Autodesk Fusion 360 part; units mm, degrees
(part 4 of 7)
equation "d92 = abs(( 1 ) * ( ( ( 1 ) * jointNodeQ * sqrt(2) - bodyWidth / 2 * cos(0 deg) + ( ( 1 ) * nodeHalfWidth ) * sin(0 deg) ) + ( 0.833333333333333 ) * ( ( 1 ) * endNodeX - ( ( 1 ) * jointNodeQ * sqrt(2) - bodyWidth / 2 * cos(0 deg) + ( ( 1 ) * nodeHalfWidth ) * sin(0 deg) ) ) ) + ( 0 ) * ( ( 1 ) * nodeHalfWidth ))"
equation "d93 = abs(( 0 ) * ( ( ( 1 ) * jointNodeQ * sqrt(2) - bodyWidth / 2 * cos(0 deg) + ( ( 1 ) * nodeHalfWidth ) * sin(0 deg) ) + ( 0.833333333333333 ) * ( ( 1 ) * endNodeX - ( ( 1 ) * jointNodeQ * sqrt(2) - bodyWidth / 2 * cos(0 deg) + ( ( 1 ) * nodeHalfWidth ) * sin(0 deg) ) ) ) + ( -1 ) * ( ( 1 ) * nodeHalfWidth ))"
equation "d94 = abs(( 1 ) * ( ( ( 1 ) * jointNodeQ * sqrt(2) - bodyWidth / 2 * cos(0 deg) + ( ( -1 ) * nodeHalfWidth ) * sin(0 deg) ) + ( 1 ) * ( ( 1 ) * endNodeX - ( ( 1 ) * jointNodeQ * sqrt(2) - bodyWidth / 2 * cos(0 deg) + ( ( -1 ) * nodeHalfWidth ) * sin(0 deg) ) ) ) + ( 0 ) * ( ( -1 ) * nodeHalfWidth ))"
equation "d95 = abs(( 0 ) * ( ( ( 1 ) * jointNodeQ * sqrt(2) - bodyWidth / 2 * cos(0 deg) + ( ( -1 ) * nodeHalfWidth ) * sin(0 deg) ) + ( 1 ) * ( ( 1 ) * endNodeX - ( ( 1 ) * jointNodeQ * sqrt(2) - bodyWidth / 2 * cos(0 deg) + ( ( -1 ) * nodeHalfWidth ) * sin(0 deg) ) ) ) + ( -1 ) * ( ( -1 ) * nodeHalfWidth ))"
equation "d96 = -memberWidth / 2"
equation "d97 = -( wall + 0.2 mm )"
equation "d99 = abs(( 1 ) * ( ( ( 1 ) * jointNodeQ * sqrt(2) - bodyWidth / 2 * cos(0 deg) + ( ( 1 ) * nodeHalfWidth ) * sin(0 deg) ) + ( 0.833333333333333 ) * ( ( 1 ) * endNodeX - ( ( 1 ) * jointNodeQ * sqrt(2) - bodyWidth / 2 * cos(0 deg) + ( ( 1 ) * nodeHalfWidth ) * sin(0 deg) ) ) ) + ( 0 ) * ( ( 1 ) * nodeHalfWidth ))"
equation "d100 = abs(( 0 ) * ( ( ( 1 ) * jointNodeQ * sqrt(2) - bodyWidth / 2 * cos(0 deg) + ( ( 1 ) * nodeHalfWidth ) * sin(0 deg) ) + ( 0.833333333333333 ) * ( ( 1 ) * endNodeX - ( ( 1 ) * jointNodeQ * sqrt(2) - bodyWidth / 2 * cos(0 deg) + ( ( 1 ) * nodeHalfWidth ) * sin(0 deg) ) ) ) + ( -1 ) * ( ( 1 ) * nodeHalfWidth ))"
equation "d101 = abs(( 1 ) * ( ( ( 1 ) * jointNodeQ * sqrt(2) - bodyWidth / 2 * cos(0 deg) + ( ( -1 ) * nodeHalfWidth ) * sin(0 deg) ) + ( 1 ) * ( ( 1 ) * endNodeX - ( ( 1 ) * jointNodeQ * sqrt(2) - bodyWidth / 2 * cos(0 deg) + ( ( -1 ) * nodeHalfWidth ) * sin(0 deg) ) ) ) + ( 0 ) * ( ( -1 ) * nodeHalfWidth ))"
equation "d102 = abs(( 0 ) * ( ( ( 1 ) * jointNodeQ * sqrt(2) - bodyWidth / 2 * cos(0 deg) + ( ( -1 ) * nodeHalfWidth ) * sin(0 deg) ) + ( 1 ) * ( ( 1 ) * endNodeX - ( ( 1 ) * jointNodeQ * sqrt(2) - bodyWidth / 2 * cos(0 deg) + ( ( -1 ) * nodeHalfWidth ) * sin(0 deg) ) ) ) + ( -1 ) * ( ( -1 ) * nodeHalfWidth ))"
equation "d103 = abs(( 1 ) * ( ( ( 1 ) * jointNodeQ * sqrt(2) - bodyWidth / 2 * cos(0 deg) + ( ( 1 ) * nodeHalfWidth ) * sin(0 deg) ) + ( 1 ) * ( ( 1 ) * endNodeX - ( ( 1 ) * jointNodeQ * sqrt(2) - bodyWidth / 2 * cos(0 deg) + ( ( 1 ) * nodeHalfWidth ) * sin(0 deg) ) ) ) + ( 0 ) * ( ( 1 ) * nodeHalfWidth ))"
equation "d104 = abs(( 0 ) * ( ( ( 1 ) * jointNodeQ * sqrt(2) - bodyWidth / 2 * cos(0 deg) + ( ( 1 ) * nodeHalfWidth ) * sin(0 deg) ) + ( 1 ) * ( ( 1 ) * endNodeX - ( ( 1 ) * jointNodeQ * sqrt(2) - bodyWidth / 2 * cos(0 deg) + ( ( 1 ) * nodeHalfWidth ) * sin(0 deg) ) ) ) + ( -1 ) * ( ( 1 ) * nodeHalfWidth ))"
equation "d105 = memberWidth / 2"
equation "d106 = -( wall + 0.2 mm )"
equation "d109 = apertureRadius"
equation "d112 = bodyWidth / 2"
equation "d114 = abs(( 1 ) * ( ( ( 1 ) * jointNodeQ * sqrt(2) - bodyWidth / 2 * cos(45 deg) + ( ( -1 ) * nodeHalfWidth ) * sin(45 deg) ) + ( 0 ) * ( ( 1 ) * endNodeX - ( ( 1 ) * jointNodeQ * sqrt(2) - bodyWidth / 2 * cos(45 deg) + ( ( -1 ) * nodeHalfWidth ) * sin(45 deg) ) ) ) + ( 0 ) * ( ( -1 ) * nodeHalfWidth ))"
equation "d115 = abs(( 0 ) * ( ( ( 1 ) * jointNodeQ * sqrt(2) - bodyWidth / 2 * cos(45 deg) + ( ( -1 ) * nodeHalfWidth ) * sin(45 deg) ) + ( 0 ) * ( ( 1 ) * endNodeX - ( ( 1 ) * jointNodeQ * sqrt(2) - bodyWidth / 2 * cos(45 deg) + ( ( -1 ) * nodeHalfWidth ) * sin(45 deg) ) ) ) + ( -1 ) * ( ( -1 ) * nodeHalfWidth ))"
equation "d116 = abs(( 1 ) * ( ( ( 1 ) * jointNodeQ * sqrt(2) - bodyWidth / 2 * cos(45 deg) + ( ( 1 ) * nodeHalfWidth ) * sin(45 deg) ) + ( 0 ) * ( ( 1 ) * endNodeX - ( ( 1 ) * jointNodeQ * sqrt(2) - bodyWidth / 2 * cos(45 deg) + ( ( 1 ) * nodeHalfWidth ) * sin(45 deg) ) ) ) + ( 0 ) * ( ( 1 ) * nodeHalfWidth ))"
equation "d117 = abs(( 0 ) * ( ( ( 1 ) * jointNodeQ * sqrt(2) - bodyWidth / 2 * cos(45 deg) + ( ( 1 ) * nodeHalfWidth ) * sin(45 deg) ) + ( 0 ) * ( ( 1 ) * endNodeX - ( ( 1 ) * jointNodeQ * sqrt(2) - bodyWidth / 2 * cos(45 deg) + ( ( 1 ) * nodeHalfWidth ) * sin(45 deg) ) ) ) + ( -1 ) * ( ( 1 ) * nodeHalfWidth ))"
equation "d118 = abs(( 1 ) * ( ( ( 1 ) * jointNodeQ * sqrt(2) - bodyWidth / 2 * cos(45 deg) + ( ( -1 ) * nodeHalfWidth ) * sin(45 deg) ) + ( 0.333333333333333 ) * ( ( 1 ) * endNodeX - ( ( 1 ) * jointNodeQ * sqrt(2) - bodyWidth / 2 * cos(45 deg) + ( ( -1 ) * nodeHalfWidth ) * sin(45 deg) ) ) ) + ( 0 ) * ( ( -1 ) * nodeHalfWidth ))"
equation "d119 = abs(( 0 ) * ( ( ( 1 ) * jointNodeQ * sqrt(2) - bodyWidth / 2 * cos(45 deg) + ( ( -1 ) * nodeHalfWidth ) * sin(45 deg) ) + ( 0.333333333333333 ) * ( ( 1 ) * endNodeX - ( ( 1 ) * jointNodeQ * sqrt(2) - bodyWidth / 2 * cos(45 deg) + ( ( -1 ) * nodeHalfWidth ) * sin(45 deg) ) ) ) + ( -1 ) * ( ( -1 ) * nodeHalfWidth ))"
equation "d120 = -memberWidth / 2"
equation "d121 = -( wall + 0.2 mm )"
equation "d123 = abs(( 1 ) * ( ( ( 1 ) * jointNodeQ * sqrt(2) - bodyWidth / 2 * cos(45 deg) + ( ( 1 ) * nodeHalfWidth ) * sin(45 deg) ) + ( 0 ) * ( ( 1 ) * endNodeX - ( ( 1 ) * jointNodeQ * sqrt(2) - bodyWidth / 2 * cos(45 deg) + ( ( 1 ) * nodeHalfWidth ) * sin(45 deg) ) ) ) + ( 0 ) * ( ( 1 ) * nodeHalfWidth ))"
equation "d124 = abs(( 0 ) * ( ( ( 1 ) * jointNodeQ * sqrt(2) - bodyWidth / 2 * cos(45 deg) + ( ( 1 ) * nodeHalfWidth ) * sin(45 deg) ) + ( 0 ) * ( ( 1 ) * endNodeX - ( ( 1 ) * jointNodeQ * sqrt(2) - bodyWidth / 2 * cos(45 deg) + ( ( 1 ) * nodeHalfWidth ) * sin(45 deg) ) ) ) + ( -1 ) * ( ( 1 ) * nodeHalfWidth ))"
equation "d125 = abs(( 1 ) * ( ( ( 1 ) * jointNodeQ * sqrt(2) - bodyWidth / 2 * cos(45 deg) + ( ( -1 ) * nodeHalfWidth ) * sin(45 deg) ) + ( 0.333333333333333 ) * ( ( 1 ) * endNodeX - ( ( 1 ) * jointNodeQ * sqrt(2) - bodyWidth / 2 * cos(45 deg) + ( ( -1 ) * nodeHalfWidth ) * sin(45 deg) ) ) ) + ( 0 ) * ( ( -1 ) * nodeHalfWidth ))"
equation "d126 = abs(( 0 ) * ( ( ( 1 ) * jointNodeQ * sqrt(2) - bodyWidth / 2 * cos(45 deg) + ( ( -1 ) * nodeHalfWidth ) * sin(45 deg) ) + ( 0.333333333333333 ) * ( ( 1 ) * endNodeX - ( ( 1 ) * jointNodeQ * sqrt(2) - bodyWidth / 2 * cos(45 deg) + ( ( -1 ) * nodeHalfWidth ) * sin(45 deg) ) ) ) + ( -1 ) * ( ( -1 ) * nodeHalfWidth ))"
equation "d127 = abs(( 1 ) * ( ( ( 1 ) * jointNodeQ * sqrt(2) - bodyWidth / 2 * cos(45 deg) + ( ( 1 ) * nodeHalfWidth ) * sin(45 deg) ) + ( 0.666666666666667 ) * ( ( 1 ) * endNodeX - ( ( 1 ) * jointNodeQ * sqrt(2) - bodyWidth / 2 * cos(45 deg) + ( ( 1 ) * nodeHalfWidth ) * sin(45 deg) ) ) ) + ( 0 ) * ( ( 1 ) * nodeHalfWidth ))"
equation "d128 = abs(( 0 ) * ( ( ( 1 ) * jointNodeQ * sqrt(2) - bodyWidth / 2 * cos(45 deg) + ( ( 1 ) * nodeHalfWidth ) * sin(45 deg) ) + ( 0.666666666666667 ) * ( ( 1 ) * endNodeX - ( ( 1 ) * jointNodeQ * sqrt(2) - bodyWidth / 2 * cos(45 deg) + ( ( 1 ) * nodeHalfWidth ) * sin(45 deg) ) ) ) + ( -1 ) * ( ( 1 ) * nodeHalfWidth ))"
equation "d129 = memberWidth / 2"
equation "d130 = -( wall + 0.2 mm )"
equation "d132 = abs(( 1 ) * ( ( ( 1 ) * jointNodeQ * sqrt(2) - bodyWidth / 2 * cos(45 deg) + ( ( -1 ) * nodeHalfWidth ) * sin(45 deg) ) + ( 0.333333333333333 ) * ( ( 1 ) * endNodeX - ( ( 1 ) * jointNodeQ * sqrt(2) - bodyWidth / 2 * cos(45 deg) + ( ( -1 ) * nodeHalfWidth ) * sin(45 deg) ) ) ) + ( 0 ) * ( ( -1 ) * nodeHalfWidth ))"
equation "d133 = abs(( 0 ) * ( ( ( 1 ) * jointNodeQ * sqrt(2) - bodyWidth / 2 * cos(45 deg) + ( ( -1 ) * nodeHalfWidth ) * sin(45 deg) ) + ( 0.333333333333333 ) * ( ( 1 ) * endNodeX - ( ( 1 ) * jointNodeQ * sqrt(2) - bodyWidth / 2 * cos(45 deg) + ( ( -1 ) * nodeHalfWidth ) * sin(45 deg) ) ) ) + ( -1 ) * ( ( -1 ) * nodeHalfWidth ))"
equation "d134 = abs(( 1 ) * ( ( ( 1 ) * jointNodeQ * sqrt(2) - bodyWidth / 2 * cos(45 deg) + ( ( 1 ) * nodeHalfWidth ) * sin(45 deg) ) + ( 0.666666666666667 ) * ( ( 1 ) * endNodeX - ( ( 1 ) * jointNodeQ * sqrt(2) - bodyWidth / 2 * cos(45 deg) + ( ( 1 ) * nodeHalfWidth ) * sin(45 deg) ) ) ) + ( 0 ) * ( ( 1 ) * nodeHalfWidth ))"
equation "d135 = abs(( 0 ) * ( ( ( 1 ) * jointNodeQ * sqrt(2) - bodyWidth / 2 * cos(45 deg) + ( ( 1 ) * nodeHalfWidth ) * sin(45 deg) ) + ( 0.666666666666667 ) * ( ( 1 ) * endNodeX - ( ( 1 ) * jointNodeQ * sqrt(2) - bodyWidth / 2 * cos(45 deg) + ( ( 1 ) * nodeHalfWidth ) * sin(45 deg) ) ) ) + ( -1 ) * ( ( 1 ) * nodeHalfWidth ))"
equation "d136 = abs(( 1 ) * ( ( ( 1 ) * jointNodeQ * sqrt(2) - bodyWidth / 2 * cos(45 deg) + ( ( -1 ) * nodeHalfWidth ) * sin(45 deg) ) + ( 1 ) * ( ( 1 ) * endNodeX - ( ( 1 ) * jointNodeQ * sqrt(2) - bodyWidth / 2 * cos(45 deg) + ( ( -1 ) * nodeHalfWidth ) * sin(45 deg) ) ) ) + ( 0 ) * ( ( -1 ) * nodeHalfWidth ))"
equation "d137 = abs(( 0 ) * ( ( ( 1 ) * jointNodeQ * sqrt(2) - bodyWidth / 2 * cos(45 deg) + ( ( -1 ) * nodeHalfWidth ) * sin(45 deg) ) + ( 1 ) * ( ( 1 ) * endNodeX - ( ( 1 ) * jointNodeQ * sqrt(2) - bodyWidth / 2 * cos(45 deg) + ( ( -1 ) * nodeHalfWidth ) * sin(45 deg) ) ) ) + ( -1 ) * ( ( -1 ) * nodeHalfWidth ))"
equation "d138 = -memberWidth / 2"
equation "d139 = -( wall + 0.2 mm )"
equation "d141 = abs(( 1 ) * ( ( ( 1 ) * jointNodeQ * sqrt(2) - bodyWidth / 2 * cos(45 deg) + ( ( 1 ) * nodeHalfWidth ) * sin(45 deg) ) + ( 0.666666666666667 ) * ( ( 1 ) * endNodeX - ( ( 1 ) * jointNodeQ * sqrt(2) - bodyWidth / 2 * cos(45 deg) + ( ( 1 ) * nodeHalfWidth ) * sin(45 deg) ) ) ) + ( 0 ) * ( ( 1 ) * nodeHalfWidth ))"
equation "d142 = abs(( 0 ) * ( ( ( 1 ) * jointNodeQ * sqrt(2) - bodyWidth / 2 * cos(45 deg) + ( ( 1 ) * nodeHalfWidth ) * sin(45 deg) ) + ( 0.666666666666667 ) * ( ( 1 ) * endNodeX - ( ( 1 ) * jointNodeQ * sqrt(2) - bodyWidth / 2 * cos(45 deg) + ( ( 1 ) * nodeHalfWidth ) * sin(45 deg) ) ) ) + ( -1 ) * ( ( 1 ) * nodeHalfWidth ))"
equation "d143 = abs(( 1 ) * ( ( ( 1 ) * jointNodeQ * sqrt(2) - bodyWidth / 2 * cos(45 deg) + ( ( -1 ) * nodeHalfWidth ) * sin(45 deg) ) + ( 1 ) * ( ( 1 ) * endNodeX - ( ( 1 ) * jointNodeQ * sqrt(2) - bodyWidth / 2 * cos(45 deg) + ( ( -1 ) * nodeHalfWidth ) * sin(45 deg) ) ) ) + ( 0 ) * ( ( -1 ) * nodeHalfWidth ))"
equation "d144 = abs(( 0 ) * ( ( ( 1 ) * jointNodeQ * sqrt(2) - bodyWidth / 2 * cos(45 deg) + ( ( -1 ) * nodeHalfWidth ) * sin(45 deg) ) + ( 1 ) * ( ( 1 ) * endNodeX - ( ( 1 ) * jointNodeQ * sqrt(2) - bodyWidth / 2 * cos(45 deg) + ( ( -1 ) * nodeHalfWidth ) * sin(45 deg) ) ) ) + ( -1 ) * ( ( -1 ) * nodeHalfWidth ))"
equation "d145 = abs(( 1 ) * ( ( ( 1 ) * jointNodeQ * sqrt(2) - bodyWidth / 2 * cos(45 deg) + ( ( 1 ) * nodeHalfWidth ) * sin(45 deg) ) + ( 1 ) * ( ( 1 ) * endNodeX - ( ( 1 ) * jointNodeQ * sqrt(2) - bodyWidth / 2 * cos(45 deg) + ( ( 1 ) * nodeHalfWidth ) * sin(45 deg) ) ) ) + ( 0 ) * ( ( 1 ) * nodeHalfWidth ))"
equation "d146 = abs(( 0 ) * ( ( ( 1 ) * jointNodeQ * sqrt(2) - bodyWidth / 2 * cos(45 deg) + ( ( 1 ) * nodeHalfWidth ) * sin(45 deg) ) + ( 1 ) * ( ( 1 ) * endNodeX - ( ( 1 ) * jointNodeQ * sqrt(2) - bodyWidth / 2 * cos(45 deg) + ( ( 1 ) * nodeHalfWidth ) * sin(45 deg) ) ) ) + ( -1 ) * ( ( 1 ) * nodeHalfWidth ))"
equation "d147 = memberWidth / 2"
equation "d148 = -( wall + 0.2 mm )"
equation "d151 = apertureRadius"
equation "d154 = bodyWidth / 2"
equation "d156 = abs(( 1 ) * ( ( ( 1 ) * jointNodeQ * sqrt(2) - bodyWidth / 2 * cos(90 deg) + ( ( -1 ) * nodeHalfWidth ) * sin(90 deg) ) + ( 0 ) * ( ( 1 ) * endNodeX - ( ( 1 ) * jointNodeQ * sqrt(2) - bodyWidth / 2 * cos(90 deg) + ( ( -1 ) * nodeHalfWidth ) * sin(90 deg) ) ) ) + ( 0 ) * ( ( -1 ) * nodeHalfWidth ))"
equation "d157 = abs(( 0 ) * ( ( ( 1 ) * jointNodeQ * sqrt(2) - bodyWidth / 2 * cos(90 deg) + ( ( -1 ) * nodeHalfWidth ) * sin(90 deg) ) + ( 0 ) * ( ( 1 ) * endNodeX - ( ( 1 ) * jointNodeQ * sqrt(2) - bodyWidth / 2 * cos(90 deg) + ( ( -1 ) * nodeHalfWidth ) * sin(90 deg) ) ) ) + ( -1 ) * ( ( -1 ) * nodeHalfWidth ))"
equation "d158 = abs(( 1 ) * ( ( ( 1 ) * jointNodeQ * sqrt(2) - bodyWidth / 2 * cos(90 deg) + ( ( 1 ) * nodeHalfWidth ) * sin(90 deg) ) + ( 0 ) * ( ( 1 ) * endNodeX - ( ( 1 ) * jointNodeQ * sqrt(2) - bodyWidth / 2 * cos(90 deg) + ( ( 1 ) * nodeHalfWidth ) * sin(90 deg) ) ) ) + ( 0 ) * ( ( 1 ) * nodeHalfWidth ))"
equation "d159 = abs(( 0 ) * ( ( ( 1 ) * jointNodeQ * sqrt(2) - bodyWidth / 2 * cos(90 deg) + ( ( 1 ) * nodeHalfWidth ) * sin(90 deg) ) + ( 0 ) * ( ( 1 ) * endNodeX - ( ( 1 ) * jointNodeQ * sqrt(2) - bodyWidth / 2 * cos(90 deg) + ( ( 1 ) * nodeHalfWidth ) * sin(90 deg) ) ) ) + ( -1 ) * ( ( 1 ) * nodeHalfWidth ))"
equation "d160 = abs(( 1 ) * ( ( ( 1 ) * jointNodeQ * sqrt(2) - bodyWidth / 2 * cos(90 deg) + ( ( -1 ) * nodeHalfWidth ) * sin(90 deg) ) + ( 0.5 ) * ( ( 1 ) * endNodeX - ( ( 1 ) * jointNodeQ * sqrt(2) - bodyWidth / 2 * cos(90 deg) + ( ( -1 ) * nodeHalfWidth ) * sin(90 deg) ) ) ) + ( 0 ) * ( ( -1 ) * nodeHalfWidth ))"
equation "d161 = abs(( 0 ) * ( ( ( 1 ) * jointNodeQ * sqrt(2) - bodyWidth / 2 * cos(90 deg) + ( ( -1 ) * nodeHalfWidth ) * sin(90 deg) ) + ( 0.5 ) * ( ( 1 ) * endNodeX - ( ( 1 ) * jointNodeQ * sqrt(2) - bodyWidth / 2 * cos(90 deg) + ( ( -1 ) * nodeHalfWidth ) * sin(90 deg) ) ) ) + ( -1 ) * ( ( -1 ) * nodeHalfWidth ))"
equation "d162 = -memberWidth / 2"
equation "d163 = -( wall + 0.2 mm )"
equation "d165 = abs(( 1 ) * ( ( ( 1 ) * jointNodeQ * sqrt(2) - bodyWidth / 2 * cos(90 deg) + ( ( 1 ) * nodeHalfWidth ) * sin(90 deg) ) + ( 0 ) * ( ( 1 ) * endNodeX - ( ( 1 ) * jointNodeQ * sqrt(2) - bodyWidth / 2 * cos(90 deg) + ( ( 1 ) * nodeHalfWidth ) * sin(90 deg) ) ) ) + ( 0 ) * ( ( 1 ) * nodeHalfWidth ))"
equation "d166 = abs(( 0 ) * ( ( ( 1 ) * jointNodeQ * sqrt(2) - bodyWidth / 2 * cos(90 deg) + ( ( 1 ) * nodeHalfWidth ) * sin(90 deg) ) + ( 0 ) * ( ( 1 ) * endNodeX - ( ( 1 ) * jointNodeQ * sqrt(2) - bodyWidth / 2 * cos(90 deg) + ( ( 1 ) * nodeHalfWidth ) * sin(90 deg) ) ) ) + ( -1 ) * ( ( 1 ) * nodeHalfWidth ))"
equation "d167 = abs(( 1 ) * ( ( ( 1 ) * jointNodeQ * sqrt(2) - bodyWidth / 2 * cos(90 deg) + ( ( -1 ) * nodeHalfWidth ) * sin(90 deg) ) + ( 0.5 ) * ( ( 1 ) * endNodeX - ( ( 1 ) * jointNodeQ * sqrt(2) - bodyWidth / 2 * cos(90 deg) + ( ( -1 ) * nodeHalfWidth ) * sin(90 deg) ) ) ) + ( 0 ) * ( ( -1 ) * nodeHalfWidth ))"
equation "d168 = abs(( 0 ) * ( ( ( 1 ) * jointNodeQ * sqrt(2) - bodyWidth / 2 * cos(90 deg) + ( ( -1 ) * nodeHalfWidth ) * sin(90 deg) ) + ( 0.5 ) * ( ( 1 ) * endNodeX - ( ( 1 ) * jointNodeQ * sqrt(2) - bodyWidth / 2 * cos(90 deg) + ( ( -1 ) * nodeHalfWidth ) * sin(90 deg) ) ) ) + ( -1 ) * ( ( -1 ) * nodeHalfWidth ))"
equation "d169 = abs(( 1 ) * ( ( ( 1 ) * jointNodeQ * sqrt(2) - bodyWidth / 2 * cos(90 deg) + ( ( 1 ) * nodeHalfWidth ) * sin(90 deg) ) + ( 1 ) * ( ( 1 ) * endNodeX - ( ( 1 ) * jointNodeQ * sqrt(2) - bodyWidth / 2 * cos(90 deg) + ( ( 1 ) * nodeHalfWidth ) * sin(90 deg) ) ) ) + ( 0 ) * ( ( 1 ) * nodeHalfWidth ))"
equation "d170 = abs(( 0 ) * ( ( ( 1 ) * jointNodeQ * sqrt(2) - bodyWidth / 2 * cos(90 deg) + ( ( 1 ) * nodeHalfWidth ) * sin(90 deg) ) + ( 1 ) * ( ( 1 ) * endNodeX - ( ( 1 ) * jointNodeQ * sqrt(2) - bodyWidth / 2 * cos(90 deg) + ( ( 1 ) * nodeHalfWidth ) * sin(90 deg) ) ) ) + ( -1 ) * ( ( 1 ) * nodeHalfWidth ))"
equation "d171 = memberWidth / 2"
equation "d172 = -( wall + 0.2 mm )"
equation "d174 = abs(( 1 ) * ( ( ( 1 ) * jointNodeQ * sqrt(2) - bodyWidth / 2 * cos(90 deg) + ( ( -1 ) * nodeHalfWidth ) * sin(90 deg) ) + ( 0.5 ) * ( ( 1 ) * endNodeX - ( ( 1 ) * jointNodeQ * sqrt(2) - bodyWidth / 2 * cos(90 deg) + ( ( -1 ) * nodeHalfWidth ) * sin(90 deg) ) ) ) + ( 0 ) * ( ( -1 ) * nodeHalfWidth ))"
equation "d175 = abs(( 0 ) * ( ( ( 1 ) * jointNodeQ * sqrt(2) - bodyWidth / 2 * cos(90 deg) + ( ( -1 ) * nodeHalfWidth ) * sin(90 deg) ) + ( 0.5 ) * ( ( 1 ) * endNodeX - ( ( 1 ) * jointNodeQ * sqrt(2) - bodyWidth / 2 * cos(90 deg) + ( ( -1 ) * nodeHalfWidth ) * sin(90 deg) ) ) ) + ( -1 ) * ( ( -1 ) * nodeHalfWidth ))"
equation "d176 = abs(( 1 ) * ( ( ( 1 ) * jointNodeQ * sqrt(2) - bodyWidth / 2 * cos(90 deg) + ( ( 1 ) * nodeHalfWidth ) * sin(90 deg) ) + ( 1 ) * ( ( 1 ) * endNodeX - ( ( 1 ) * jointNodeQ * sqrt(2) - bodyWidth / 2 * cos(90 deg) + ( ( 1 ) * nodeHalfWidth ) * sin(90 deg) ) ) ) + ( 0 ) * ( ( 1 ) * nodeHalfWidth ))"
equation "d177 = abs(( 0 ) * ( ( ( 1 ) * jointNodeQ * sqrt(2) - bodyWidth / 2 * cos(90 deg) + ( ( 1 ) * nodeHalfWidth ) * sin(90 deg) ) + ( 1 ) * ( ( 1 ) * endNodeX - ( ( 1 ) * jointNodeQ * sqrt(2) - bodyWidth / 2 * cos(90 deg) + ( ( 1 ) * nodeHalfWidth ) * sin(90 deg) ) ) ) + ( -1 ) * ( ( 1 ) * nodeHalfWidth ))"
equation "d178 = abs(( 1 ) * ( ( ( 1 ) * jointNodeQ * sqrt(2) - bodyWidth / 2 * cos(90 deg) + ( ( -1 ) * nodeHalfWidth ) * sin(90 deg) ) + ( 1 ) * ( ( 1 ) * endNodeX - ( ( 1 ) * jointNodeQ * sqrt(2) - bodyWidth / 2 * cos(90 deg) + ( ( -1 ) * nodeHalfWidth ) * sin(90 deg) ) ) ) + ( 0 ) * ( ( -1 ) * nodeHalfWidth ))"
equation "d179 = abs(( 0 ) * ( ( ( 1 ) * jointNodeQ * sqrt(2) - bodyWidth / 2 * cos(90 deg) + ( ( -1 ) * nodeHalfWidth ) * sin(90 deg) ) + ( 1 ) * ( ( 1 ) * endNodeX - ( ( 1 ) * jointNodeQ * sqrt(2) - bodyWidth / 2 * cos(90 deg) + ( ( -1 ) * nodeHalfWidth ) * sin(90 deg) ) ) ) + ( -1 ) * ( ( -1 ) * nodeHalfWidth ))"
equation "d180 = -memberWidth / 2"
equation "d181 = -( wall + 0.2 mm )"
equation "d184 = apertureRadius"
equation "d187 = bodyWidth / 2"
equation "d189 = abs(( 1 ) * ( ( ( 1 ) * jointNodeQ * sqrt(2) - bodyWidth / 2 * cos(135 deg) + ( ( -1 ) * nodeHalfWidth ) * sin(135 deg) ) + ( 0 ) * ( ( 1 ) * endNodeX - ( ( 1 ) * jointNodeQ * sqrt(2) - bodyWidth / 2 * cos(135 deg) + ( ( -1 ) * nodeHalfWidth ) * sin(135 deg) ) ) ) + ( 0 ) * ( ( -1 ) * nodeHalfWidth ))"
equation "d190 = abs(( 0 ) * ( ( ( 1 ) * jointNodeQ * sqrt(2) - bodyWidth / 2 * cos(135 deg) + ( ( -1 ) * nodeHalfWidth ) * sin(135 deg) ) + ( 0 ) * ( ( 1 ) * endNodeX - ( ( 1 ) * jointNodeQ * sqrt(2) - bodyWidth / 2 * cos(135 deg) + ( ( -1 ) * nodeHalfWidth ) * sin(135 deg) ) ) ) + ( -1 ) * ( ( -1 ) * nodeHalfWidth ))"
equation "d191 = abs(( 1 ) * ( ( ( 1 ) * jointNodeQ * sqrt(2) - bodyWidth / 2 * cos(135 deg) + ( ( 1 ) * nodeHalfWidth ) * sin(135 deg) ) + ( 0 ) * ( ( 1 ) * endNodeX - ( ( 1 ) * jointNodeQ * sqrt(2) - bodyWidth / 2 * cos(135 deg) + ( ( 1 ) * nodeHalfWidth ) * sin(135 deg) ) ) ) + ( 0 ) * ( ( 1 ) * nodeHalfWidth ))"
equation "d192 = abs(( 0 ) * ( ( ( 1 ) * jointNodeQ * sqrt(2) - bodyWidth / 2 * cos(135 deg) + ( ( 1 ) * nodeHalfWidth ) * sin(135 deg) ) + ( 0 ) * ( ( 1 ) * endNodeX - ( ( 1 ) * jointNodeQ * sqrt(2) - bodyWidth / 2 * cos(135 deg) + ( ( 1 ) * nodeHalfWidth ) * sin(135 deg) ) ) ) + ( -1 ) * ( ( 1 ) * nodeHalfWidth ))"
equation "d193 = abs(( 1 ) * ( ( ( 1 ) * jointNodeQ * sqrt(2) - bodyWidth / 2 * cos(135 deg) + ( ( -1 ) * nodeHalfWidth ) * sin(135 deg) ) + ( 1 ) * ( ( 1 ) * endNodeX - ( ( 1 ) * jointNodeQ * sqrt(2) - bodyWidth / 2 * cos(135 deg) + ( ( -1 ) * nodeHalfWidth ) * sin(135 deg) ) ) ) + ( 0 ) * ( ( -1 ) * nodeHalfWidth ))"
equation "d194 = abs(( 0 ) * ( ( ( 1 ) * jointNodeQ * sqrt(2) - bodyWidth / 2 * cos(135 deg) + ( ( -1 ) * nodeHalfWidth ) * sin(135 deg) ) + ( 1 ) * ( ( 1 ) * endNodeX - ( ( 1 ) * jointNodeQ * sqrt(2) - bodyWidth / 2 * cos(135 deg) + ( ( -1 ) * nodeHalfWidth ) * sin(135 deg) ) ) ) + ( -1 ) * ( ( -1 ) * nodeHalfWidth ))"
equation "d195 = -memberWidth / 2"
equation "d196 = -( wall + 0.2 mm )"
equation "d198 = abs(( 1 ) * ( ( ( 1 ) * jointNodeQ * sqrt(2) - bodyWidth / 2 * cos(135 deg) + ( ( 1 ) * nodeHalfWidth ) * sin(135 deg) ) + ( 0 ) * ( ( 1 ) * endNodeX - ( ( 1 ) * jointNodeQ * sqrt(2) - bodyWidth / 2 * cos(135 deg) + ( ( 1 ) * nodeHalfWidth ) * sin(135 deg) ) ) ) + ( 0 ) * ( ( 1 ) * nodeHalfWidth ))"
equation "d199 = abs(( 0 ) * ( ( ( 1 ) * jointNodeQ * sqrt(2) - bodyWidth / 2 * cos(135 deg) + ( ( 1 ) * nodeHalfWidth ) * sin(135 deg) ) + ( 0 ) * ( ( 1 ) * endNodeX - ( ( 1 ) * jointNodeQ * sqrt(2) - bodyWidth / 2 * cos(135 deg) + ( ( 1 ) * nodeHalfWidth ) * sin(135 deg) ) ) ) + ( -1 ) * ( ( 1 ) * nodeHalfWidth ))"
equation "d200 = abs(( 1 ) * ( ( ( 1 ) * jointNodeQ * sqrt(2) - bodyWidth / 2 * cos(135 deg) + ( ( -1 ) * nodeHalfWidth ) * sin(135 deg) ) + ( 1 ) * ( ( 1 ) * endNodeX - ( ( 1 ) * jointNodeQ * sqrt(2) - bodyWidth / 2 * cos(135 deg) + ( ( -1 ) * nodeHalfWidth ) * sin(135 deg) ) ) ) + ( 0 ) * ( ( -1 ) * nodeHalfWidth ))"
equation "d201 = abs(( 0 ) * ( ( ( 1 ) * jointNodeQ * sqrt(2) - bodyWidth / 2 * cos(135 deg) + ( ( -1 ) * nodeHalfWidth ) * sin(135 deg) ) + ( 1 ) * ( ( 1 ) * endNodeX - ( ( 1 ) * jointNodeQ * sqrt(2) - bodyWidth / 2 * cos(135 deg) + ( ( -1 ) * nodeHalfWidth ) * sin(135 deg) ) ) ) + ( -1 ) * ( ( -1 ) * nodeHalfWidth ))"
equation "d202 = abs(( 1 ) * ( ( ( 1 ) * jointNodeQ * sqrt(2) - bodyWidth / 2 * cos(135 deg) + ( ( 1 ) * nodeHalfWidth ) * sin(135 deg) ) + ( 1 ) * ( ( 1 ) * endNodeX - ( ( 1 ) * jointNodeQ * sqrt(2) - bodyWidth / 2 * cos(135 deg) + ( ( 1 ) * nodeHalfWidth ) * sin(135 deg) ) ) ) + ( 0 ) * ( ( 1 ) * nodeHalfWidth ))"
equation "d203 = abs(( 0 ) * ( ( ( 1 ) * jointNodeQ * sqrt(2) - bodyWidth / 2 * cos(135 deg) + ( ( 1 ) * nodeHalfWidth ) * sin(135 deg) ) + ( 1 ) * ( ( 1 ) * endNodeX - ( ( 1 ) * jointNodeQ * sqrt(2) - bodyWidth / 2 * cos(135 deg) + ( ( 1 ) * nodeHalfWidth ) * sin(135 deg) ) ) ) + ( -1 ) * ( ( 1 ) * nodeHalfWidth ))"
equation "d204 = memberWidth / 2"
equation "d205 = -( wall + 0.2 mm )"
equation "d208 = apertureRadius"
equation "d211 = bodyWidth / 2"
equation "d213 = abs(( -1 ) * ( ( ( 1 ) * jointNodeQ * sqrt(2) - bodyWidth / 2 * cos(180 deg) + ( ( -1 ) * nodeHalfWidth ) * sin(180 deg) ) + ( 0 ) * ( ( 1 ) * endNodeX - ( ( 1 ) * jointNodeQ * sqrt(2) - bodyWidth / 2 * cos(180 deg) + ( ( -1 ) * nodeHalfWidth ) * sin(180 deg) ) ) ) + ( 0 ) * ( ( -1 ) * nodeHalfWidth ))"
equation "d214 = abs(( 0 ) * ( ( ( 1 ) * jointNodeQ * sqrt(2) - bodyWidth / 2 * cos(180 deg) + ( ( -1 ) * nodeHalfWidth ) * sin(180 deg) ) + ( 0 ) * ( ( 1 ) * endNodeX - ( ( 1 ) * jointNodeQ * sqrt(2) - bodyWidth / 2 * cos(180 deg) + ( ( -1 ) * nodeHalfWidth ) * sin(180 deg) ) ) ) + ( 1 ) * ( ( -1 ) * nodeHalfWidth ))"
equation "d215 = abs(( -1 ) * ( ( ( 1 ) * jointNodeQ * sqrt(2) - bodyWidth / 2 * cos(180 deg) + ( ( 1 ) * nodeHalfWidth ) * sin(180 deg) ) + ( 0 ) * ( ( 1 ) * endNodeX - ( ( 1 ) * jointNodeQ * sqrt(2) - bodyWidth / 2 * cos(180 deg) + ( ( 1 ) * nodeHalfWidth ) * sin(180 deg) ) ) ) + ( 0 ) * ( ( 1 ) * nodeHalfWidth ))"
equation "d216 = abs(( 0 ) * ( ( ( 1 ) * jointNodeQ * sqrt(2) - bodyWidth / 2 * cos(180 deg) + ( ( 1 ) * nodeHalfWidth ) * sin(180 deg) ) + ( 0 ) * ( ( 1 ) * endNodeX - ( ( 1 ) * jointNodeQ * sqrt(2) - bodyWidth / 2 * cos(180 deg) + ( ( 1 ) * nodeHalfWidth ) * sin(180 deg) ) ) ) + ( 1 ) * ( ( 1 ) * nodeHalfWidth ))"
equation "d217 = abs(( -1 ) * ( ( ( 1 ) * jointNodeQ * sqrt(2) - bodyWidth / 2 * cos(180 deg) + ( ( -1 ) * nodeHalfWidth ) * sin(180 deg) ) + ( 1 ) * ( ( 1 ) * endNodeX - ( ( 1 ) * jointNodeQ * sqrt(2) - bodyWidth / 2 * cos(180 deg) + ( ( -1 ) * nodeHalfWidth ) * sin(180 deg) ) ) ) + ( 0 ) * ( ( -1 ) * nodeHalfWidth ))"
equation "d218 = abs(( 0 ) * ( ( ( 1 ) * jointNodeQ * sqrt(2) - bodyWidth / 2 * cos(180 deg) + ( ( -1 ) * nodeHalfWidth ) * sin(180 deg) ) + ( 1 ) * ( ( 1 ) * endNodeX - ( ( 1 ) * jointNodeQ * sqrt(2) - bodyWidth / 2 * cos(180 deg) + ( ( -1 ) * nodeHalfWidth ) * sin(180 deg) ) ) ) + ( 1 ) * ( ( -1 ) * nodeHalfWidth ))"
equation "d219 = -memberWidth / 2"
equation "d220 = -( wall + 0.2 mm )"
equation "d222 = abs(( -1 ) * ( ( ( 1 ) * jointNodeQ * sqrt(2) - bodyWidth / 2 * cos(180 deg) + ( ( 1 ) * nodeHalfWidth ) * sin(180 deg) ) + ( 0 ) * ( ( 1 ) * endNodeX - ( ( 1 ) * jointNodeQ * sqrt(2) - bodyWidth / 2 * cos(180 deg) + ( ( 1 ) * nodeHalfWidth ) * sin(180 deg) ) ) ) + ( 0 ) * ( ( 1 ) * nodeHalfWidth ))"
equation "d223 = abs(( 0 ) * ( ( ( 1 ) * jointNodeQ * sqrt(2) - bodyWidth / 2 * cos(180 deg) + ( ( 1 ) * nodeHalfWidth ) * sin(180 deg) ) + ( 0 ) * ( ( 1 ) * endNodeX - ( ( 1 ) * jointNodeQ * sqrt(2) - bodyWidth / 2 * cos(180 deg) + ( ( 1 ) * nodeHalfWidth ) * sin(180 deg) ) ) ) + ( 1 ) * ( ( 1 ) * nodeHalfWidth ))"
equation "d224 = abs(( -1 ) * ( ( ( 1 ) * jointNodeQ * sqrt(2) - bodyWidth / 2 * cos(180 deg) + ( ( -1 ) * nodeHalfWidth ) * sin(180 deg) ) + ( 1 ) * ( ( 1 ) * endNodeX - ( ( 1 ) * jointNodeQ * sqrt(2) - bodyWidth / 2 * cos(180 deg) + ( ( -1 ) * nodeHalfWidth ) * sin(180 deg) ) ) ) + ( 0 ) * ( ( -1 ) * nodeHalfWidth ))"
equation "d225 = abs(( 0 ) * ( ( ( 1 ) * jointNodeQ * sqrt(2) - bodyWidth / 2 * cos(180 deg) + ( ( -1 ) * nodeHalfWidth ) * sin(180 deg) ) + ( 1 ) * ( ( 1 ) * endNodeX - ( ( 1 ) * jointNodeQ * sqrt(2) - bodyWidth / 2 * cos(180 deg) + ( ( -1 ) * nodeHalfWidth ) * sin(180 deg) ) ) ) + ( 1 ) * ( ( -1 ) * nodeHalfWidth ))"
equation "d226 = abs(( -1 ) * ( ( ( 1 ) * jointNodeQ * sqrt(2) - bodyWidth / 2 * cos(180 deg) + ( ( 1 ) * nodeHalfWidth ) * sin(180 deg) ) + ( 1 ) * ( ( 1 ) * endNodeX - ( ( 1 ) * jointNodeQ * sqrt(2) - bodyWidth / 2 * cos(180 deg) + ( ( 1 ) * nodeHalfWidth ) * sin(180 deg) ) ) ) + ( 0 ) * ( ( 1 ) * nodeHalfWidth ))"
equation "d227 = abs(( 0 ) * ( ( ( 1 ) * jointNodeQ * sqrt(2) - bodyWidth / 2 * cos(180 deg) + ( ( 1 ) * nodeHalfWidth ) * sin(180 deg) ) + ( 1 ) * ( ( 1 ) * endNodeX - ( ( 1 ) * jointNodeQ * sqrt(2) - bodyWidth / 2 * cos(180 deg) + ( ( 1 ) * nodeHalfWidth ) * sin(180 deg) ) ) ) + ( 1 ) * ( ( 1 ) * nodeHalfWidth ))"
equation "d228 = memberWidth / 2"
equation "d229 = -( wall + 0.2 mm )"
equation "d232 = apertureRadius"
equation "d235 = bodyWidth / 2"
equation "d237 = abs(( 1 ) * ( ( ( 1 ) * jointNodeQ * sqrt(2) - bodyWidth / 2 * cos(225 deg) + ( ( -1 ) * nodeHalfWidth ) * sin(225 deg) ) + ( 0 ) * ( ( 1 ) * endNodeX - ( ( 1 ) * jointNodeQ * sqrt(2) - bodyWidth / 2 * cos(225 deg) + ( ( -1 ) * nodeHalfWidth ) * sin(225 deg) ) ) ) + ( 0 ) * ( ( -1 ) * nodeHalfWidth ))"
equation "d238 = abs(( 0 ) * ( ( ( 1 ) * jointNodeQ * sqrt(2) - bodyWidth / 2 * cos(225 deg) + ( ( -1 ) * nodeHalfWidth ) * sin(225 deg) ) + ( 0 ) * ( ( 1 ) * endNodeX - ( ( 1 ) * jointNodeQ * sqrt(2) - bodyWidth / 2 * cos(225 deg) + ( ( -1 ) * nodeHalfWidth ) * sin(225 deg) ) ) ) + ( -1 ) * ( ( -1 ) * nodeHalfWidth ))"
equation "d239 = abs(( 1 ) * ( ( ( 1 ) * jointNodeQ * sqrt(2) - bodyWidth / 2 * cos(225 deg) + ( ( 1 ) * nodeHalfWidth ) * sin(225 deg) ) + ( 0 ) * ( ( 1 ) * endNodeX - ( ( 1 ) * jointNodeQ * sqrt(2) - bodyWidth / 2 * cos(225 deg) + ( ( 1 ) * nodeHalfWidth ) * sin(225 deg) ) ) ) + ( 0 ) * ( ( 1 ) * nodeHalfWidth ))"
equation "d240 = abs(( 0 ) * ( ( ( 1 ) * jointNodeQ * sqrt(2) - bodyWidth / 2 * cos(225 deg) + ( ( 1 ) * nodeHalfWidth ) * sin(225 deg) ) + ( 0 ) * ( ( 1 ) * endNodeX - ( ( 1 ) * jointNodeQ * sqrt(2) - bodyWidth / 2 * cos(225 deg) + ( ( 1 ) * nodeHalfWidth ) * sin(225 deg) ) ) ) + ( -1 ) * ( ( 1 ) * nodeHalfWidth ))"
equation "d241 = abs(( 1 ) * ( ( ( 1 ) * jointNodeQ * sqrt(2) - bodyWidth / 2 * cos(225 deg) + ( ( -1 ) * nodeHalfWidth ) * sin(225 deg) ) + ( 1 ) * ( ( 1 ) * endNodeX - ( ( 1 ) * jointNodeQ * sqrt(2) - bodyWidth / 2 * cos(225 deg) + ( ( -1 ) * nodeHalfWidth ) * sin(225 deg) ) ) ) + ( 0 ) * ( ( -1 ) * nodeHalfWidth ))"
equation "d242 = abs(( 0 ) * ( ( ( 1 ) * jointNodeQ * sqrt(2) - bodyWidth / 2 * cos(225 deg) + ( ( -1 ) * nodeHalfWidth ) * sin(225 deg) ) + ( 1 ) * ( ( 1 ) * endNodeX - ( ( 1 ) * jointNodeQ * sqrt(2) - bodyWidth / 2 * cos(225 deg) + ( ( -1 ) * nodeHalfWidth ) * sin(225 deg) ) ) ) + ( -1 ) * ( ( -1 ) * nodeHalfWidth ))"
equation "d243 = -memberWidth / 2"
equation "d244 = -( wall + 0.2 mm )"
equation "d246 = abs(( 1 ) * ( ( ( 1 ) * jointNodeQ * sqrt(2) - bodyWidth / 2 * cos(225 deg) + ( ( 1 ) * nodeHalfWidth ) * sin(225 deg) ) + ( 0 ) * ( ( 1 ) * endNodeX - ( ( 1 ) * jointNodeQ * sqrt(2) - bodyWidth / 2 * cos(225 deg) + ( ( 1 ) * nodeHalfWidth ) * sin(225 deg) ) ) ) + ( 0 ) * ( ( 1 ) * nodeHalfWidth ))"
equation "d247 = abs(( 0 ) * ( ( ( 1 ) * jointNodeQ * sqrt(2) - bodyWidth / 2 * cos(225 deg) + ( ( 1 ) * nodeHalfWidth ) * sin(225 deg) ) + ( 0 ) * ( ( 1 ) * endNodeX - ( ( 1 ) * jointNodeQ * sqrt(2) - bodyWidth / 2 * cos(225 deg) + ( ( 1 ) * nodeHalfWidth ) * sin(225 deg) ) ) ) + ( -1 ) * ( ( 1 ) * nodeHalfWidth ))"
equation "d248 = abs(( 1 ) * ( ( ( 1 ) * jointNodeQ * sqrt(2) - bodyWidth / 2 * cos(225 deg) + ( ( -1 ) * nodeHalfWidth ) * sin(225 deg) ) + ( 1 ) * ( ( 1 ) * endNodeX - ( ( 1 ) * jointNodeQ * sqrt(2) - bodyWidth / 2 * cos(225 deg) + ( ( -1 ) * nodeHalfWidth ) * sin(225 deg) ) ) ) + ( 0 ) * ( ( -1 ) * nodeHalfWidth ))"
equation "d249 = abs(( 0 ) * ( ( ( 1 ) * jointNodeQ * sqrt(2) - bodyWidth / 2 * cos(225 deg) + ( ( -1 ) * nodeHalfWidth ) * sin(225 deg) ) + ( 1 ) * ( ( 1 ) * endNodeX - ( ( 1 ) * jointNodeQ * sqrt(2) - bodyWidth / 2 * cos(225 deg) + ( ( -1 ) * nodeHalfWidth ) * sin(225 deg) ) ) ) + ( -1 ) * ( ( -1 ) * nodeHalfWidth ))"
equation "d250 = abs(( 1 ) * ( ( ( 1 ) * jointNodeQ * sqrt(2) - bodyWidth / 2 * cos(225 deg) + ( ( 1 ) * nodeHalfWidth ) * sin(225 deg) ) + ( 1 ) * ( ( 1 ) * endNodeX - ( ( 1 ) * jointNodeQ * sqrt(2) - bodyWidth / 2 * cos(225 deg) + ( ( 1 ) * nodeHalfWidth ) * sin(225 deg) ) ) ) + ( 0 ) * ( ( 1 ) * nodeHalfWidth ))"
equation "d251 = abs(( 0 ) * ( ( ( 1 ) * jointNodeQ * sqrt(2) - bodyWidth / 2 * cos(225 deg) + ( ( 1 ) * nodeHalfWidth ) * sin(225 deg) ) + ( 1 ) * ( ( 1 ) * endNodeX - ( ( 1 ) * jointNodeQ * sqrt(2) - bodyWidth / 2 * cos(225 deg) + ( ( 1 ) * nodeHalfWidth ) * sin(225 deg) ) ) ) + ( -1 ) * ( ( 1 ) * nodeHalfWidth ))"
equation "d252 = memberWidth / 2"
equation "d253 = -( wall + 0.2 mm )"
equation "d256 = apertureRadius"
equation "d259 = bodyWidth / 2"
equation "d261 = abs(( -1 ) * ( ( ( 1 ) * jointNodeQ * sqrt(2) - bodyWidth / 2 * cos(270 deg) + ( ( -1 ) * nodeHalfWidth ) * sin(270 deg) ) + ( 0 ) * ( ( 1 ) * endNodeX - ( ( 1 ) * jointNodeQ * sqrt(2) - bodyWidth / 2 * cos(270 deg) + ( ( -1 ) * nodeHalfWidth ) * sin(270 deg) ) ) ) + ( 0 ) * ( ( -1 ) * nodeHalfWidth ))"
equation "d262 = abs(( 0 ) * ( ( ( 1 ) * jointNodeQ * sqrt(2) - bodyWidth / 2 * cos(270 deg) + ( ( -1 ) * nodeHalfWidth ) * sin(270 deg) ) + ( 0 ) * ( ( 1 ) * endNodeX - ( ( 1 ) * jointNodeQ * sqrt(2) - bodyWidth / 2 * cos(270 deg) + ( ( -1 ) * nodeHalfWidth ) * sin(270 deg) ) ) ) + ( 1 ) * ( ( -1 ) * nodeHalfWidth ))"
equation "d263 = abs(( -1 ) * ( ( ( 1 ) * jointNodeQ * sqrt(2) - bodyWidth / 2 * cos(270 deg) + ( ( 1 ) * nodeHalfWidth ) * sin(270 deg) ) + ( 0 ) * ( ( 1 ) * endNodeX - ( ( 1 ) * jointNodeQ * sqrt(2) - bodyWidth / 2 * cos(270 deg) + ( ( 1 ) * nodeHalfWidth ) * sin(270 deg) ) ) ) + ( 0 ) * ( ( 1 ) * nodeHalfWidth ))"
equation "d264 = abs(( 0 ) * ( ( ( 1 ) * jointNodeQ * sqrt(2) - bodyWidth / 2 * cos(270 deg) + ( ( 1 ) * nodeHalfWidth ) * sin(270 deg) ) + ( 0 ) * ( ( 1 ) * endNodeX - ( ( 1 ) * jointNodeQ * sqrt(2) - bodyWidth / 2 * cos(270 deg) + ( ( 1 ) * nodeHalfWidth ) * sin(270 deg) ) ) ) + ( 1 ) * ( ( 1 ) * nodeHalfWidth ))"
equation "d265 = abs(( -1 ) * ( ( ( 1 ) * jointNodeQ * sqrt(2) - bodyWidth / 2 * cos(270 deg) + ( ( -1 ) * nodeHalfWidth ) * sin(270 deg) ) + ( 0.5 ) * ( ( 1 ) * endNodeX - ( ( 1 ) * jointNodeQ * sqrt(2) - bodyWidth / 2 * cos(270 deg) + ( ( -1 ) * nodeHalfWidth ) * sin(270 deg) ) ) ) + ( 0 ) * ( ( -1 ) * nodeHalfWidth ))"
equation "d266 = abs(( 0 ) * ( ( ( 1 ) * jointNodeQ * sqrt(2) - bodyWidth / 2 * cos(270 deg) + ( ( -1 ) * nodeHalfWidth ) * sin(270 deg) ) + ( 0.5 ) * ( ( 1 ) * endNodeX - ( ( 1 ) * jointNodeQ * sqrt(2) - bodyWidth / 2 * cos(270 deg) + ( ( -1 ) * nodeHalfWidth ) * sin(270 deg) ) ) ) + ( 1 ) * ( ( -1 ) * nodeHalfWidth ))"
equation "d267 = -memberWidth / 2"
equation "d268 = -( wall + 0.2 mm )"
equation "d270 = abs(( -1 ) * ( ( ( 1 ) * jointNodeQ * sqrt(2) - bodyWidth / 2 * cos(270 deg) + ( ( 1 ) * nodeHalfWidth ) * sin(270 deg) ) + ( 0 ) * ( ( 1 ) * endNodeX - ( ( 1 ) * jointNodeQ * sqrt(2) - bodyWidth / 2 * cos(270 deg) + ( ( 1 ) * nodeHalfWidth ) * sin(270 deg) ) ) ) + ( 0 ) * ( ( 1 ) * nodeHalfWidth ))"
equation "d271 = abs(( 0 ) * ( ( ( 1 ) * jointNodeQ * sqrt(2) - bodyWidth / 2 * cos(270 deg) + ( ( 1 ) * nodeHalfWidth ) * sin(270 deg) ) + ( 0 ) * ( ( 1 ) * endNodeX - ( ( 1 ) * jointNodeQ * sqrt(2) - bodyWidth / 2 * cos(270 deg) + ( ( 1 ) * nodeHalfWidth ) * sin(270 deg) ) ) ) + ( 1 ) * ( ( 1 ) * nodeHalfWidth ))"
equation "d272 = abs(( -1 ) * ( ( ( 1 ) * jointNodeQ * sqrt(2) - bodyWidth / 2 * cos(270 deg) + ( ( -1 ) * nodeHalfWidth ) * sin(270 deg) ) + ( 0.5 ) * ( ( 1 ) * endNodeX - ( ( 1 ) * jointNodeQ * sqrt(2) - bodyWidth / 2 * cos(270 deg) + ( ( -1 ) * nodeHalfWidth ) * sin(270 deg) ) ) ) + ( 0 ) * ( ( -1 ) * nodeHalfWidth ))"
equation "d273 = abs(( 0 ) * ( ( ( 1 ) * jointNodeQ * sqrt(2) - bodyWidth / 2 * cos(270 deg) + ( ( -1 ) * nodeHalfWidth ) * sin(270 deg) ) + ( 0.5 ) * ( ( 1 ) * endNodeX - ( ( 1 ) * jointNodeQ * sqrt(2) - bodyWidth / 2 * cos(270 deg) + ( ( -1 ) * nodeHalfWidth ) * sin(270 deg) ) ) ) + ( 1 ) * ( ( -1 ) * nodeHalfWidth ))"
equation "d274 = abs(( -1 ) * ( ( ( 1 ) * jointNodeQ * sqrt(2) - bodyWidth / 2 * cos(270 deg) + ( ( 1 ) * nodeHalfWidth ) * sin(270 deg) ) + ( 1 ) * ( ( 1 ) * endNodeX - ( ( 1 ) * jointNodeQ * sqrt(2) - bodyWidth / 2 * cos(270 deg) + ( ( 1 ) * nodeHalfWidth ) * sin(270 deg) ) ) ) + ( 0 ) * ( ( 1 ) * nodeHalfWidth ))"
equation "d275 = abs(( 0 ) * ( ( ( 1 ) * jointNodeQ * sqrt(2) - bodyWidth / 2 * cos(270 deg) + ( ( 1 ) * nodeHalfWidth ) * sin(270 deg) ) + ( 1 ) * ( ( 1 ) * endNodeX - ( ( 1 ) * jointNodeQ * sqrt(2) - bodyWidth / 2 * cos(270 deg) + ( ( 1 ) * nodeHalfWidth ) * sin(270 deg) ) ) ) + ( 1 ) * ( ( 1 ) * nodeHalfWidth ))"
equation "d276 = memberWidth / 2"
equation "d277 = -( wall + 0.2 mm )"
equation "d279 = abs(( -1 ) * ( ( ( 1 ) * jointNodeQ * sqrt(2) - bodyWidth / 2 * cos(270 deg) + ( ( -1 ) * nodeHalfWidth ) * sin(270 deg) ) + ( 0.5 ) * ( ( 1 ) * endNodeX - ( ( 1 ) * jointNodeQ * sqrt(2) - bodyWidth / 2 * cos(270 deg) + ( ( -1 ) * nodeHalfWidth ) * sin(270 deg) ) ) ) + ( 0 ) * ( ( -1 ) * nodeHalfWidth ))"
equation "d280 = abs(( 0 ) * ( ( ( 1 ) * jointNodeQ * sqrt(2) - bodyWidth / 2 * cos(270 deg) + ( ( -1 ) * nodeHalfWidth ) * sin(270 deg) ) + ( 0.5 ) * ( ( 1 ) * endNodeX - ( ( 1 ) * jointNodeQ * sqrt(2) - bodyWidth / 2 * cos(270 deg) + ( ( -1 ) * nodeHalfWidth ) * sin(270 deg) ) ) ) + ( 1 ) * ( ( -1 ) * nodeHalfWidth ))"
equation "d281 = abs(( -1 ) * ( ( ( 1 ) * jointNodeQ * sqrt(2) - bodyWidth / 2 * cos(270 deg) + ( ( 1 ) * nodeHalfWidth ) * sin(270 deg) ) + ( 1 ) * ( ( 1 ) * endNodeX - ( ( 1 ) * jointNodeQ * sqrt(2) - bodyWidth / 2 * cos(270 deg) + ( ( 1 ) * nodeHalfWidth ) * sin(270 deg) ) ) ) + ( 0 ) * ( ( 1 ) * nodeHalfWidth ))"
equation "d282 = abs(( 0 ) * ( ( ( 1 ) * jointNodeQ * sqrt(2) - bodyWidth / 2 * cos(270 deg) + ( ( 1 ) * nodeHalfWidth ) * sin(270 deg) ) + ( 1 ) * ( ( 1 ) * endNodeX - ( ( 1 ) * jointNodeQ * sqrt(2) - bodyWidth / 2 * cos(270 deg) + ( ( 1 ) * nodeHalfWidth ) * sin(270 deg) ) ) ) + ( 1 ) * ( ( 1 ) * nodeHalfWidth ))"
equation "d283 = abs(( -1 ) * ( ( ( 1 ) * jointNodeQ * sqrt(2) - bodyWidth / 2 * cos(270 deg) + ( ( -1 ) * nodeHalfWidth ) * sin(270 deg) ) + ( 1 ) * ( ( 1 ) * endNodeX - ( ( 1 ) * jointNodeQ * sqrt(2) - bodyWidth / 2 * cos(270 deg) + ( ( -1 ) * nodeHalfWidth ) * sin(270 deg) ) ) ) + ( 0 ) * ( ( -1 ) * nodeHalfWidth ))"
equation "d284 = abs(( 0 ) * ( ( ( 1 ) * jointNodeQ * sqrt(2) - bodyWidth / 2 * cos(270 deg) + ( ( -1 ) * nodeHalfWidth ) * sin(270 deg) ) + ( 1 ) * ( ( 1 ) * endNodeX - ( ( 1 ) * jointNodeQ * sqrt(2) - bodyWidth / 2 * cos(270 deg) + ( ( -1 ) * nodeHalfWidth ) * sin(270 deg) ) ) ) + ( 1 ) * ( ( -1 ) * nodeHalfWidth ))"
equation "d285 = -memberWidth / 2"
equation "d286 = -( wall + 0.2 mm )"
equation "d289 = apertureRadius"
equation "d292 = bodyWidth / 2"
equation "d294 = abs(( 1 ) * ( ( ( 1 ) * jointNodeQ * sqrt(2) - bodyWidth / 2 * cos(315 deg) + ( ( -1 ) * nodeHalfWidth ) * sin(315 deg) ) + ( 0 ) * ( ( 1 ) * endNodeX - ( ( 1 ) * jointNodeQ * sqrt(2) - bodyWidth / 2 * cos(315 deg) + ( ( -1 ) * nodeHalfWidth ) * sin(315 deg) ) ) ) + ( 0 ) * ( ( -1 ) * nodeHalfWidth ))"
equation "d295 = abs(( 0 ) * ( ( ( 1 ) * jointNodeQ * sqrt(2) - bodyWidth / 2 * cos(315 deg) + ( ( -1 ) * nodeHalfWidth ) * sin(315 deg) ) + ( 0 ) * ( ( 1 ) * endNodeX - ( ( 1 ) * jointNodeQ * sqrt(2) - bodyWidth / 2 * cos(315 deg) + ( ( -1 ) * nodeHalfWidth ) * sin(315 deg) ) ) ) + ( -1 ) * ( ( -1 ) * nodeHalfWidth ))"
equation "d296 = abs(( 1 ) * ( ( ( 1 ) * jointNodeQ * sqrt(2) - bodyWidth / 2 * cos(315 deg) + ( ( 1 ) * nodeHalfWidth ) * sin(315 deg) ) + ( 0 ) * ( ( 1 ) * endNodeX - ( ( 1 ) * jointNodeQ * sqrt(2) - bodyWidth / 2 * cos(315 deg) + ( ( 1 ) * nodeHalfWidth ) * sin(315 deg) ) ) ) + ( 0 ) * ( ( 1 ) * nodeHalfWidth ))"
equation "d297 = abs(( 0 ) * ( ( ( 1 ) * jointNodeQ * sqrt(2) - bodyWidth / 2 * cos(315 deg) + ( ( 1 ) * nodeHalfWidth ) * sin(315 deg) ) + ( 0 ) * ( ( 1 ) * endNodeX - ( ( 1 ) * jointNodeQ * sqrt(2) - bodyWidth / 2 * cos(315 deg) + ( ( 1 ) * nodeHalfWidth ) * sin(315 deg) ) ) ) + ( -1 ) * ( ( 1 ) * nodeHalfWidth ))"
equation "d298 = abs(( 1 ) * ( ( ( 1 ) * jointNodeQ * sqrt(2) - bodyWidth / 2 * cos(315 deg) + ( ( -1 ) * nodeHalfWidth ) * sin(315 deg) ) + ( 0.333333333333333 ) * ( ( 1 ) * endNodeX - ( ( 1 ) * jointNodeQ * sqrt(2) - bodyWidth / 2 * cos(315 deg) + ( ( -1 ) * nodeHalfWidth ) * sin(315 deg) ) ) ) + ( 0 ) * ( ( -1 ) * nodeHalfWidth ))"
equation "d299 = abs(( 0 ) * ( ( ( 1 ) * jointNodeQ * sqrt(2) - bodyWidth / 2 * cos(315 deg) + ( ( -1 ) * nodeHalfWidth ) * sin(315 deg) ) + ( 0.333333333333333 ) * ( ( 1 ) * endNodeX - ( ( 1 ) * jointNodeQ * sqrt(2) - bodyWidth / 2 * cos(315 deg) + ( ( -1 ) * nodeHalfWidth ) * sin(315 deg) ) ) ) + ( -1 ) * ( ( -1 ) * nodeHalfWidth ))"
equation "d300 = -memberWidth / 2"